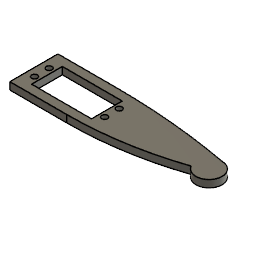
dogcalff3d (Autodesk Fusion 360 design; units mm, degrees)
part number: 2026-04-03-12-31-24-931
Autodesk Fusion 360 part; units mm, degrees
sketch "Sketch1" plane through (0, 0, 0) normal (0, 1, 0) x (1, 0, 0)
  line L0 (0, 0) -> (0, 33)
  line L1 (0, 33) -> (39, 33)
  line L2 (0, 0) -> (39, 0)
  arc A0 (120, 25.5) -> (39, 33) centre (39, -408.15) ccw
  arc A1 (39, 0) -> (112.2058, 12) centre (39, 229.2952) ccw
  arc A2 (112.2058, 12) -> (120, 25.5) centre (120, 16.5) ccw
  arc A3 (112.2058, 12) -> (120, 25.5) centre (120, 16.5) ccw
  line L3 (0, 33) -> (0, 21.5)
  circle A4 centre (5.5, 21.5) radius 2
  circle A5 centre (5.5, 11.5) radius 2
  circle A6 centre (53.5, 21.5) radius 2
  circle A7 centre (53.5, 11.5) radius 2
  line L4 (0, 33) -> (6, 33)
  line L5 (0, 33) -> (9, 33)
  line L6 (9, 27) -> (50, 27)
  line L7 (50, 27) -> (50, 6)
  line L8 (50, 6) -> (9, 6)
  line L9 (9, 6) -> (9, 27)
  dimension "d1" = 33
  dimension "d2" = 39
  dimension "d3" = 39
  dimension "d5" = 18
  dimension "d8" = 11.5
  dimension "d9" = 4
  dimension "d10" = 10
  dimension "d11" = 4
  dimension "d12" = 48
  dimension "d13" = 48
  dimension "d14" = 4
  dimension "d15" = 4
  dimension "d16" = 6
  dimension "d19" = 9
  dimension "d20" = 6
  dimension "d22" = 41
  dimension "d23" = 21
  constraint coincident L0.start L2.start
  constraint vertical L0
  constraint perpendicular L0 L1
  constraint perpendicular L0 L2
  constraint tangent L1 A0
  constraint concentric A2 A3
  constraint tangent L2 A1
  constraint perpendicular L1 L3
  constraint perpendicular L0 L4
  constraint perpendicular L0 L5
  constraint horizontal L6
  constraint vertical L7
  constraint horizontal L8
  constraint vertical L9
  measures "d1" distance of L0.start L0.end
  measures "d2" distance of L0.end L1.end
  measures "d3" distance of L0.start L2.end
  measures "d5" diameter of A3
  measures "d8" distance of L0.end L3.end
  measures "d9" diameter of A4
  measures "d10" distance of A4.centre A5.centre
  measures "d11" diameter of A5
  measures "d12" distance of A4.centre A6.centre
  measures "d13" distance of A5.centre A7.centre
  measures "d14" diameter of A6
  measures "d15" diameter of A7
  measures "d16" distance of L0.end L4.end
  measures "d19" distance of L0.end L5.end
  measures "d20" distance of L5.end L6.start
  measures "d22" distance of L6.start L6.end
  measures "d23" distance of L6.start L8.end
sketch "Sketch2" plane through (0, 0, 0) normal (0, 1, 0) x (1, 0, 0)
extrude "Extrude1" add sketch "Sketch1" along normal blind 5
sketch "Sketch4" plane through (0, 0, 0) normal (0, 1, 0) x (1, 0, 0)
  line L0 (55.371, 25.7542) -> (116.652, 26.2623) construction
  line L1 (116.652, 26.2623) -> (116.7459, 14.9391) construction
  line L2 (116.7459, 14.9391) -> (55.4649, 14.4311) construction
  line L3 (55.4649, 14.4311) -> (55.371, 25.7542) construction
  dimension "d28" = 5
  text T0 "GRIET Idea Lab" font "Arial" height 5 align centre top in box 61.2831 x 11.3235 at (55.371, 25.7542) x (0.999966, 0.00829) y (0.00829, -0.999966) spacing 1 kerned
extrude "Extrude2" add sketch "Sketch4" against normal blind 2 text T0
equation "d29 = 'GRIET Idea Lab'"
